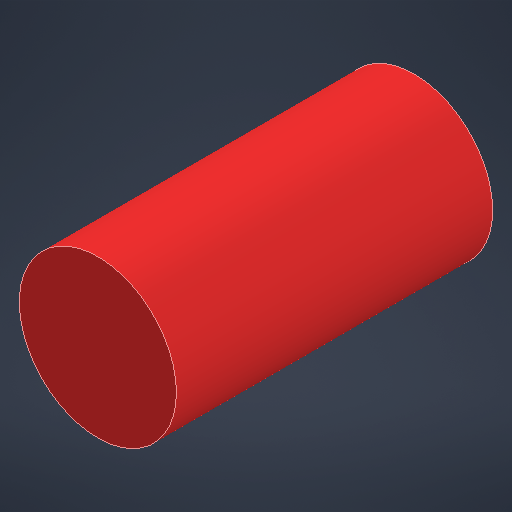
# Autodesk Inventor part: ref_stop
Saved by Autodesk Inventor 2027.1 (Build 311270010, 270A)
## iProperties
Created: 2026-10-22
Part Number: ref_stop
Material: 일반
Document SubType Name: Modeling
Designer: sungjun
Density: 1 g/cm^3
Appearance: ref_stop_c
Author: sungjun
Autodesk Inventor part; units mm, degrees
ref_plane "YZ Plane" through (0, 0, 0) normal (1, 0, 0) x (0, 1, 0)
ref_plane "XZ Plane" through (0, 0, 0) normal (0, 1, 0) x (-1, 0, 0)
ref_plane "작업 평면1" through (0, 0, 46) normal (0, 0, 1) x (1, 0, 0)
sketch "스케치1" plane through (0, 0, 46) normal (0, 0, 1) x (1, 0, 0)
  circle A0 centre (86, 17.65) radius 7.7
  constraints: 1 centre point
extrude "돌출1" add sketch "스케치1" along normal mid plane 31
